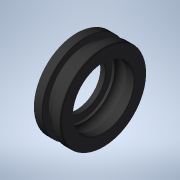
# Autodesk Inventor part: 101013DH-16-B1_or
Saved by Autodesk Inventor 2021 (Build 250183000, 183)
## iProperties
Created: 2025-04-11
Part Number: 101013DH-16-B1_or
Material: Generic
Catalog Web Link: www.cadenas.de
Description: DH-A,B,H or-D-Series bearings
Vendor: TOKBEARING
Document SubType Name: Modeling
Designer: psAdmin
Manufacturer: TOKBEARING
Mass: 11800 g
Surface Area: 11.4551 cm^2
Volume: 0.689994 cm^3
Density: 1 g/cm^3
Appearance: PSOLRGB-175-175-175
Category: PARTsolutions
Company: TOKBEARING
Title: 101013DH-16-B1_or
Author: Cadenas PARTsolutions
Comments: D-Series bearings
PSOL_IDENT_0: {$CADENAS_DATA/23d-libs/tok_bearing/d_series_bearings/dh_abh/dh_abh_or.prj},181 {VTYP=3D},{NB=101013
PSOL_IDENT_1: DH-16-B1_or},{LINA=101013DH-16-B1_or},{NN=DH-A,B,H or},{DATE=24.03.2025 06:05:05},{GEOMDATE=06.12.20
PSOL_IDENT_2: 12 08:06:00},{VERSION=},{LINEID=2630},{WBVAR=},{WBNUMERIC=}  {NB=101013DH-16-B1_or},{LINA=101013DH-1
PSOL_IDENT_3: 6-B1_or},{KT=DUMMY},{IDNR=},{CODE=101013},{PN=DH-16-B1},{D=19},{D1=16.0},{SD=-},{SDX=0.000},{SD1=-},
PSOL_IDENT_4: {SD1X=0.000},{W=6},{C=1},{CX=1.000},{L=8},{LX=8.000},{D2XT=-},{D2=0.000},{T=0.000},{G=2.1},{TYPE=2},
PSOL_IDENT_5: {QTY=2.000},{GW=11.8},{NDM=6.000},{BD=3},{OP=39.878},{N=6},{R=6.35},{GP=2.82}
NB: 101013DH-16-B1_or
NN: DH-A,B,H or
NT: D-Series bearings
NBSYN: $CODE.$PN._or
LINA: 101013DH-16-B1_or
CATALOG: TOK, Inc
CODE: 101013
PN: DH-16-B1
D: 19
D1: 16
SD: -
SD1: -
W: 6
C: 1
L: 8
D2XT: -
G: 2.1
TYPE: 2
QTY: 2.000
GW: 11.8
SUPPLIER: TOKBEARING
ARTICLENO: 101013DH-16-B1_or
BOMINFO: 101013DH-16-B1_or
CREATOR: CADENAS GmbH
Autodesk Inventor part; units mm, degrees
sketch "Sketch_1" plane through (0, 0, 0) normal (0, 0, 1) x (1, 0, 0)
  line L0 (6, 0) -> (0, 0)
  line L1 (0, 9.2) -> (0, 5.33)
  arc A0 (0, 5.33) -> (0.15, 5.18) centre (0.15, 5.33) ccw
  line L2 (0.15, 5.18) -> (1.05, 5.18)
  arc A1 (1.05, 5.18) -> (1.2, 5.33) centre (1.05, 5.33) ccw
  line L3 (1.2, 5.33) -> (1.2, 6.68)
  line L4 (1.2, 6.68) -> (1.701, 6.68)
  arc A2 (4.299, 6.68) -> (1.701, 6.68) centre (3, 5.93) ccw
  line L5 (4.299, 6.68) -> (5.85, 6.68)
  arc A3 (5.85, 6.68) -> (6, 6.83) centre (5.85, 6.83) ccw
  line L6 (6, 6.83) -> (6, 9.2)
  arc A4 (6, 9.2) -> (5.7, 9.5) centre (5.7, 9.2) ccw
  line L7 (5.7, 9.5) -> (4.2, 9.5)
  arc A5 (4.2, 9.5) -> (4.05, 9.35) centre (4.2, 9.35) ccw
  line L8 (4.05, 9.35) -> (4.05, 8)
  line L9 (4.05, 8) -> (1.95, 8)
  line L10 (1.95, 8) -> (1.95, 9.38)
  arc A6 (1.95, 9.38) -> (1.83, 9.5) centre (1.83, 9.38) ccw
  line L11 (1.83, 9.5) -> (0.3, 9.5)
  arc A7 (0.3, 9.5) -> (0, 9.2) centre (0.3, 9.2) ccw
  constraints: 24 end point, 16 point on circle, 8 centre point
revolve "Revolution1" add sketch "Sketch_1" angle 360 about axis through (6, 0, 0) along (1, 0, 0)
ref_plane "IR_OR_XY" through (0, 0, 0) normal (1, 0, 0) x (0, 0, -1)
ref_plane "IR_OR_YZ" through (0, 0, 0) normal (0, 0, -1) x (0, 1, 0)
ref_plane "IR_OR_ZX" through (0, 0, 0) normal (0, 1, 0) x (1, 0, 0)
ref_plane "OR_Cage_XY" through (0, 0, 0) normal (1, 0, 0) x (0, 0, -1)
ref_plane "OR_Cage_YZ" through (0, 0, 0) normal (0, 0, -1) x (0, 1, 0)
ref_plane "OR_Cage_ZX" through (0, 0, 0) normal (0, 1, 0) x (1, 0, 0)
body "Solid1"
